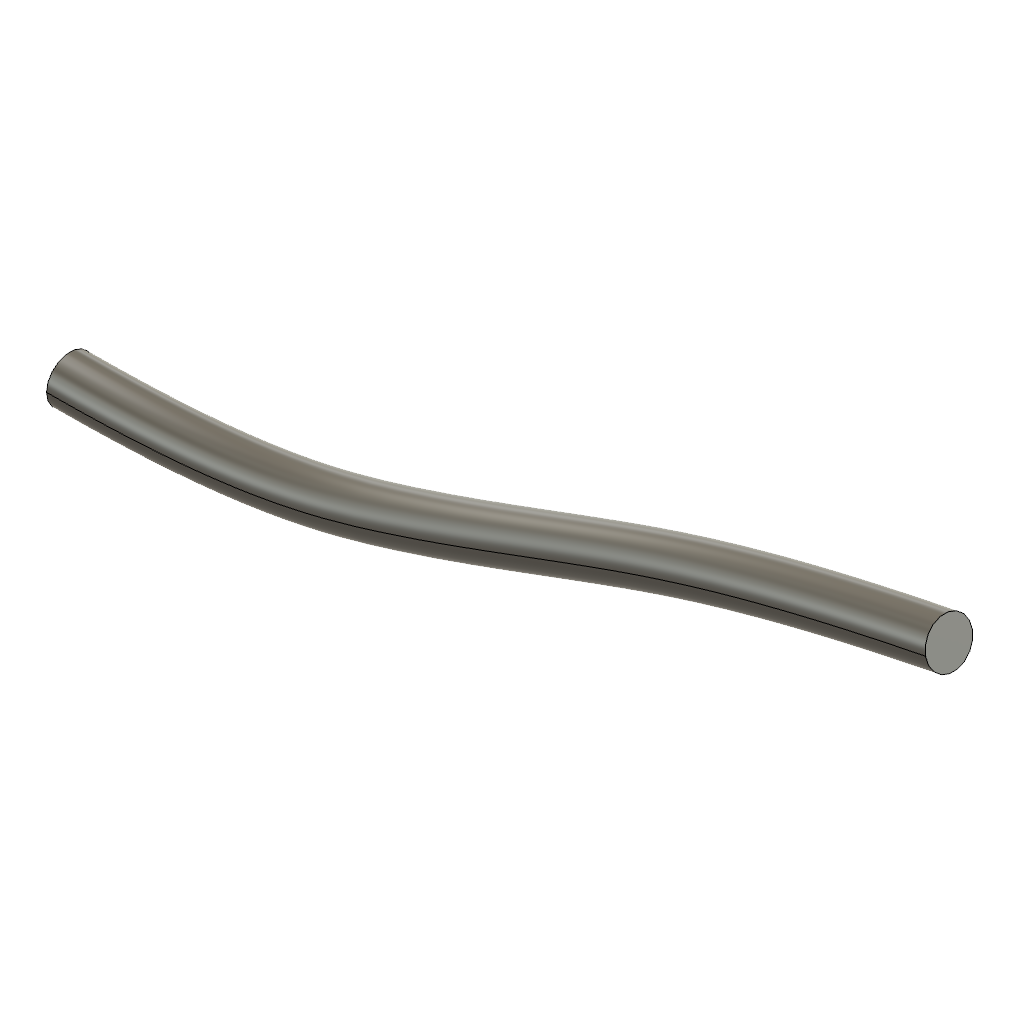
polynomial_multispan (Autodesk Fusion 360 design; units mm, degrees)
part number: 2026-10-21-16-32-34-724
Autodesk Fusion 360 part; units mm, degrees
sketch "OwnedNurbsSweepPath_polynomial_multispan" plane through (0, 0, 0) normal (0, 0, 1) x (1, 0, 0)
  spline S0 degree 3 poles (0, 0) (15, 0) (30, 4) (45, 10) (60, 15) (75, 18) knots 0 0 0 0 0.333333 0.666667 1 1 1 1
sketch "OwnedNurbsSweepCircle_polynomial_multispan" plane through (0, 0, 0) normal (1, 0, 0) x (0, 0, -1)
  circle A0 centre (0, 0) radius 2
sweep "OwnedFixedNurbsSweep_polynomial_multispan" add profiles "OwnedNurbsSweepCircle_polynomial_multispan" path "OwnedNurbsSweepPath_polynomial_multispan" along S0 section 1
